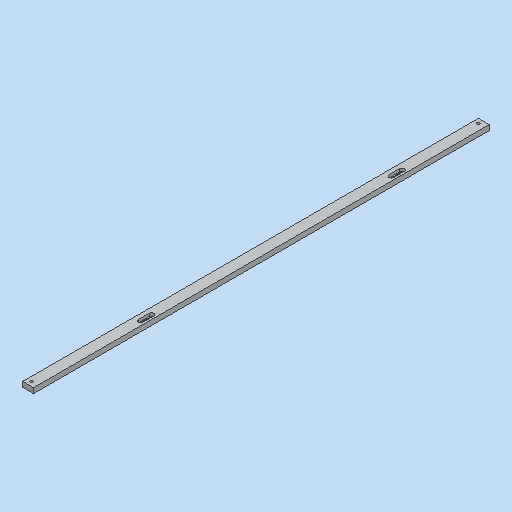
# Autodesk Inventor part: MM0948AN140_G01_121
Saved by Autodesk Inventor 2023.3 (Build 273359000, 359)
## iProperties
RuleStatus: InUse
Created: 2023-04-19
Part Number: MM0948AN140_G01_121
Material: 3.3206 AlMgSi0,5 - AW 6060
Description: =<RBPARTNOTITLE2>
Document SubType Name: Modeling
Designer: FH/Wi
Mass: 830.108 g
Surface Area: 802.335 cm^2
Volume: 307.447 cm^3
Density: 2.7 g/cm^3
Appearance: Aluminium AnP
AnP_Kategorie: 1
AnP_Material: =<Material>
MaxAbmaße: 12 x 1054 x 25 (FM)
AnP_TemplVers: 20200821
RBDOCUMENTTYPE: DRF
RBDOCUMENTVERSION: 00
RBDRAWINGMAINSCALE: 1:1
RBDRAWINGMISSINGSPEC: --
RBDRAWINGVOLUME: --
RBDSV1: 0850
RBGBEDGESIN1: +0,5
RBGBEDGESIN2: +0,2
RBGBEDGESOUT1: -0,3
RBGBEDGESOUT2: -0,1
RBMATERIAL: =<Material>
RBMATMEETS: --
RBMATNO: =<Part Number>
RBPARTMADEOF: 12 x 1054 x 25 (FM)
RBPARTNO: SIEHE MNR
RBPARTNOTITLE1: manufactured part
RBPARTNOTITLE2: Anfertigungsteil
RBPARTSAFETYINDICATOR: --
RBSURFACE: anodised colourless
RBSURFACE2: eloxiert farblos
RBZEDGESNORM: ISO13715:2002-06
RBZGENDIMCLASS: m
RBZGENDIMNORM: ISO 2768-1:1989-11
RBZGENGEOCLASS: H
RBZGENGEONORM: ISO 2768-2:1989-11
RBZSURFACENORM: ISO13D2:2002-02
RBZTOLERANCENORM: ISO 14405-1:2010-12
Author: FH/Wi
Keywords: =<RBPARTMADEOF>
Comments: =<RBSURFACE2>
Revision Number: 01
Autodesk Inventor part; units mm, degrees
ref_plane "YZ Plane" through (0, 0, 0) normal (1, 0, 0) x (0, 1, 0)
ref_plane "XZ Plane" through (0, 0, 0) normal (0, 1, 0) x (-1, 0, 0)
ref_plane "XY Plane" through (0, 0, 0) normal (0, 0, 1) x (1, 0, 0)
sketch "Skizze1" plane through (0, 0, 0) normal (0, 0, 1) x (1, 0, 0)
  line L0 (-12.5, 0) -> (12.5, 0)
  line L1 (12.5, 0) -> (12.5, -1054)
  line L2 (12.5, -1054) -> (-12.5, -1054)
  line L3 (-12.5, -1054) -> (-12.5, 0)
  point P0 (0, 0)
  point P1 (0, 0)
  dimension "d0" = 25
  dimension "d1" = 1054
  constraints: 8 end point, 2 parallel, 1 coincident, 1 horizontal, 1 midpoint, 1 perpendicular
  measures "d0" distance of L0.start L0.end
  measures "d1" distance of L2.end L0.start
extrude "Extrusion1" add sketch "Skizze1" along normal blind 12
sketch "Skizze2" plane through (0, 0, 0) normal (0, 0, -1) x (-1, 0, 0)
  line L0 (-12.5, 0) -> (12.5, 0) projected
  line L1 (12.5, -1054) -> (-12.5, -1054) projected
  line L2 (12.5, 0) -> (12.5, -1054) projected
  point P0 (2.5, -10)
  point P1 (2.5, -1044)
  dimension "d11" = 10
  dimension "d12" = 10
  dimension "d18" = 10
  constraints: 1 vertical alignment
  measures "d11" distance from line of point (2.5, -10) L0
  measures "d12" distance from line of L1 point (2.5, -1044)
  measures "d18" distance from line of L2 point (2.5, -10)
hole "Bohrung1" at (-2.5, -10, 0) at (-2.5, -1044, 0) direction (0, 0, 1) diameter 6.6 end through all counterbore diameter 11 counterbore depth 6.8 clearance for "Inbusschraube ISO 4762  versenkt" size "M6" standard "ISO"
sketch "Skizze3" plane through (0, 0, 12) normal (0, 0, 1) x (1, 0, 0)
  line L0 (2.5, -191.5) -> (2.5, -216.5) construction
  line L1 (-0.8, -191.5) -> (-0.8, -216.5)
  line L2 (5.8, -216.5) -> (5.8, -191.5)
  arc A0 (5.8, -191.5) -> (-0.8, -191.5) centre (2.5, -191.5) ccw
  arc A1 (-0.8, -216.5) -> (5.8, -216.5) centre (2.5, -216.5) ccw
  line L3 (2.5, -771.5) -> (2.5, -796.5) construction
  line L4 (-0.8, -771.5) -> (-0.8, -796.5)
  line L5 (5.8, -796.5) -> (5.8, -771.5)
  arc A2 (5.8, -771.5) -> (-0.8, -771.5) centre (2.5, -771.5) ccw
  arc A3 (-0.8, -796.5) -> (5.8, -796.5) centre (2.5, -796.5) ccw
  line L6 (12.5, 0) -> (-12.5, 0) projected
  line L7 (-12.5, 0) -> (-12.5, -1054) projected
  line L8 (-12.5, -1054) -> (12.5, -1054) projected
  point P0 (0, 0)
  point P1 (2.5, -204)
  point P2 (2.5, -784)
  dimension "d14" = 6.6
  dimension "d15" = 25
  dimension "d24" = 15
  dimension "d25" = 850
  dimension "d26" = 270
  constraints: 16 end point, 8 point on circle, 8 tangent, 4 centre point, 3 parallel, 2 collinear, 2 midpoint, 1 equal radius, 1 vertical
  measures "d14" distance between parallel lines of L1 L2
  measures "d15" distance of L2.start L2.end
  measures "d24" distance from line of L0.start L7
  measures "d25" vertical distance of L7.end point (2.5, -204)
  measures "d26" distance from line of L8 point (2.5, -784)
extrude "Extrusion2" cut sketch "Skizze3" against normal through all
sketch "Skizze4" plane through (0, 0, 12) normal (0, 0, 1) x (1, 0, 0)
  line L0 (-0.8, -216.5) -> (-0.8, -191.5) projected
  arc A0 (5.8, -191.5) -> (-0.8, -191.5) centre (2.5, -191.5) ccw projected
  line L1 (5.8, -191.5) -> (5.8, -216.5) projected
  arc A1 (-0.8, -216.5) -> (5.8, -216.5) centre (2.5, -216.5) ccw projected
  arc A2 (5.8, -771.5) -> (-0.8, -771.5) centre (2.5, -771.5) ccw projected
  line L2 (-0.8, -796.5) -> (-0.8, -771.5) projected
  line L3 (5.8, -771.5) -> (5.8, -796.5) projected
  arc A3 (-0.8, -796.5) -> (5.8, -796.5) centre (2.5, -796.5) ccw projected
  arc A4 (8, -771.5) -> (-3, -771.5) centre (2.5, -771.5) ccw
  line L4 (8, -771.5) -> (8, -796.5)
  arc A5 (-3, -796.5) -> (8, -796.5) centre (2.5, -796.5) ccw
  line L5 (-3, -796.5) -> (-3, -771.5)
  line L6 (-3, -191.5) -> (-3, -216.5)
  arc A6 (-3, -216.5) -> (8, -216.5) centre (2.5, -216.5) ccw
  line L7 (8, -216.5) -> (8, -191.5)
  arc A7 (8, -191.5) -> (-3, -191.5) centre (2.5, -191.5) ccw
  point P0 (0, 0)
  dimension "d21" = 11
  constraints: 8 end point, 8 point on circle, 4 centre point, 1 equal radius, 6 other
  measures "d21" distance between parallel lines of L7 L6
extrude "Extrusion3" cut sketch "Skizze4" against normal blind 6.8 contours L0 A0 L1 A1 | L3 A3 L2 A2 | L4 A5 L5 A4 | A7 L7 A6 L6
